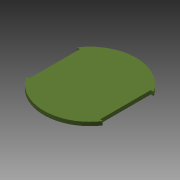
# Autodesk Inventor part: roll_body
Saved by Autodesk Inventor 2014 (Build 180170000, 170)
## iProperties
Created: 2014-09-19
Part Number: roll_body
Material: Všeobecné
Document SubType Name: Modeling
Designer: brodhaq
Density: 1 g/cm^3
Appearance: Výchozí
Author: brodhaq
Autodesk Inventor part; units mm, degrees
ref_plane "YZ Plane" through (0, 0, 0) normal (1, 0, 0) x (0, 1, 0)
ref_plane "XZ Plane" through (0, 0, 0) normal (0, 1, 0) x (-1, 0, 0)
ref_plane "XY Plane" through (0, 0, 0) normal (0, 0, 1) x (1, 0, 0)
sketch "Náčrt1" plane through (0, 0, 0) normal (0, 0, 1) x (1, 0, 0)
  arc A0 (-28.5, -20.3162) -> (28.5, -20.3162) centre (0, 0) ccw
  arc A1 (28.5, 20.3162) -> (-28.5, 20.3162) centre (0, 0) ccw
  line L0 (-28.5, -20.3162) -> (-30.5, -20.3162)
  line L1 (-28.5, 20.3162) -> (-30.5, 20.3162)
  line L2 (28.5, -20.3162) -> (30.5, -20.3162)
  line L3 (28.5, 20.3162) -> (30.5, 20.3162)
  line L4 (30.5, -20.9464) -> (30.5, -20.3162)
  line L5 (30.5, 20.3162) -> (30.5, 20.9464)
  line L6 (-30.5, 20.9464) -> (-30.5, 20.3162)
  line L7 (-30.5, -20.3162) -> (-30.5, -20.9464)
  line L8 (6.5, 9.5) -> (17.5, 9.5)
  line L9 (17.5, 9.5) -> (17.5, -9.5)
  line L10 (17.5, -9.5) -> (6.5, -9.5)
  line L11 (6.5, -9.5) -> (6.5, 9.5)
  line L12 (9.5, 6.5) -> (14.5, 6.5)
  line L13 (14.5, 6.5) -> (14.5, -6.5)
  line L14 (14.5, -6.5) -> (9.5, -6.5)
  line L15 (9.5, -6.5) -> (9.5, 6.5)
  line L16 (-4.5, -6.5) -> (2.5, -6.5)
  line L17 (2.5, -6.5) -> (2.5, 6.5)
  line L18 (2.5, 6.5) -> (-4.5, 6.5)
  line L19 (-4.5, 6.5) -> (-4.5, -6.5)
  line L20 (28.5, 20.3162) -> (28.5, -20.3162)
  line L21 (-28.5, -20.3162) -> (-28.5, 20.3162)
  arc A2 (-30.5, -20.9464) -> (30.5, -20.9464) centre (0, 0) ccw
  arc A3 (30.5, 20.9464) -> (-30.5, 20.9464) centre (0, 0) ccw
  point P0 (9.5, 0)
  point P1 (2.5, 0)
  dimension "d7" = 35
  dimension "d8" = 35
  dimension "d15" = 0
  dimension "d16" = 61
  dimension "d17" = 61
  dimension "d18" = 40.6325
  dimension "d19" = 0
  dimension "d20" = 40.6325
  dimension "d21" = 30.5
  dimension "d22" = 20.3163
  dimension "d23" = 13
  dimension "d24" = 7
  dimension "d25" = 13
  dimension "d26" = 3
  dimension "d27" = 3
  dimension "d28" = 3
  dimension "d29" = 3
  dimension "d30" = 5
  dimension "d31" = 4
  dimension "d32" = 0
  dimension "d33" = 0
  dimension "d34" = 11
  constraints: 44 end point, 11 parallel, 9 perpendicular, 8 point on circle, 4 centre point, 3 horizontal, 2 midpoint, 2 vertical, 1 coincident
  measures "d7" radius of A1
  measures "d8" radius of A0
  measures "d15" distance between parallel lines of L4 L5
  measures "d16" distance between parallel lines of L5 L6
  measures "d17" distance between parallel lines of L5 L7
  measures "d18" distance between parallel lines of L2 L3
  measures "d19" distance between parallel lines of L1 L3
  measures "d20" distance between parallel lines of L0 L3
  measures "d21" distance from line of point (0, 0) L5
  measures "d22" distance from line of point (0, 0) L3
  measures "d23" distance between parallel lines of L16 L18
  measures "d24" distance between parallel lines of L17 L19
  measures "d25" distance between parallel lines of L14 L12
  measures "d26" distance between parallel lines of L8 L12
  measures "d27" distance between parallel lines of L10 L14
  measures "d28" distance between parallel lines of L11 L15
  measures "d29" distance between parallel lines of L9 L13
  measures "d30" distance between parallel lines of L13 L15
  measures "d31" distance between parallel lines of L11 L17
  measures "d32" vertical distance of point (9.5, 0) point (2.5, 0)
  measures "d33" vertical distance of point (0, 0) point (2.5, 0)
  measures "d34" distance from line of L3.start L9
extrude "Vysunutí4" add sketch "Náčrt1" along normal blind 3 contours L21 A1 L20 A0 | A0 L2 L4 A2 L7 L0 | L1 L6 A3 L5 L3 A1 | L8 L9 L10 L11 | L12 L13 L14 L15 | L19 L18 L17 L16
extrude "Vysunutí5" add sketch "Náčrt1" against normal blind 5 contours L8 L9 L10 L11 | L19 L18 L17 L16
sketch "Náčrt2" plane through (0, 0, -5) normal (0, 0, -1) x (-1, 0, 0)
  line L0 (-2.5, -6.5) -> (4.5, -6.5) projected
  line L1 (4.5, -6.5) -> (4.5, 6.5) projected
  line L2 (4.5, 6.5) -> (-2.5, 6.5) projected
  line L3 (-2.5, 6.5) -> (-2.5, -6.5) projected
  line L4 (-2.5, 4.5) -> (2.5, 4.5)
  line L5 (2.5, 4.5) -> (2.5, -4.5)
  line L6 (2.5, -4.5) -> (-2.5, -4.5)
  line L7 (-2.5, -4.5) -> (-2.5, 4.5)
  point P0 (0, 0)
  dimension "d39" = 2
  dimension "d40" = 2
  dimension "d41" = 2
  constraints: 8 end point, 2 parallel, 1 horizontal, 1 perpendicular, 1 point on line
  measures "d39" distance between parallel lines of L2 L4
  measures "d40" distance between parallel lines of L0 L6
  measures "d41" distance between parallel lines of L1 L5
extrude "Vysunutí6" cut sketch "Náčrt2" against normal blind 4 contours L3 L4 L5 L6
